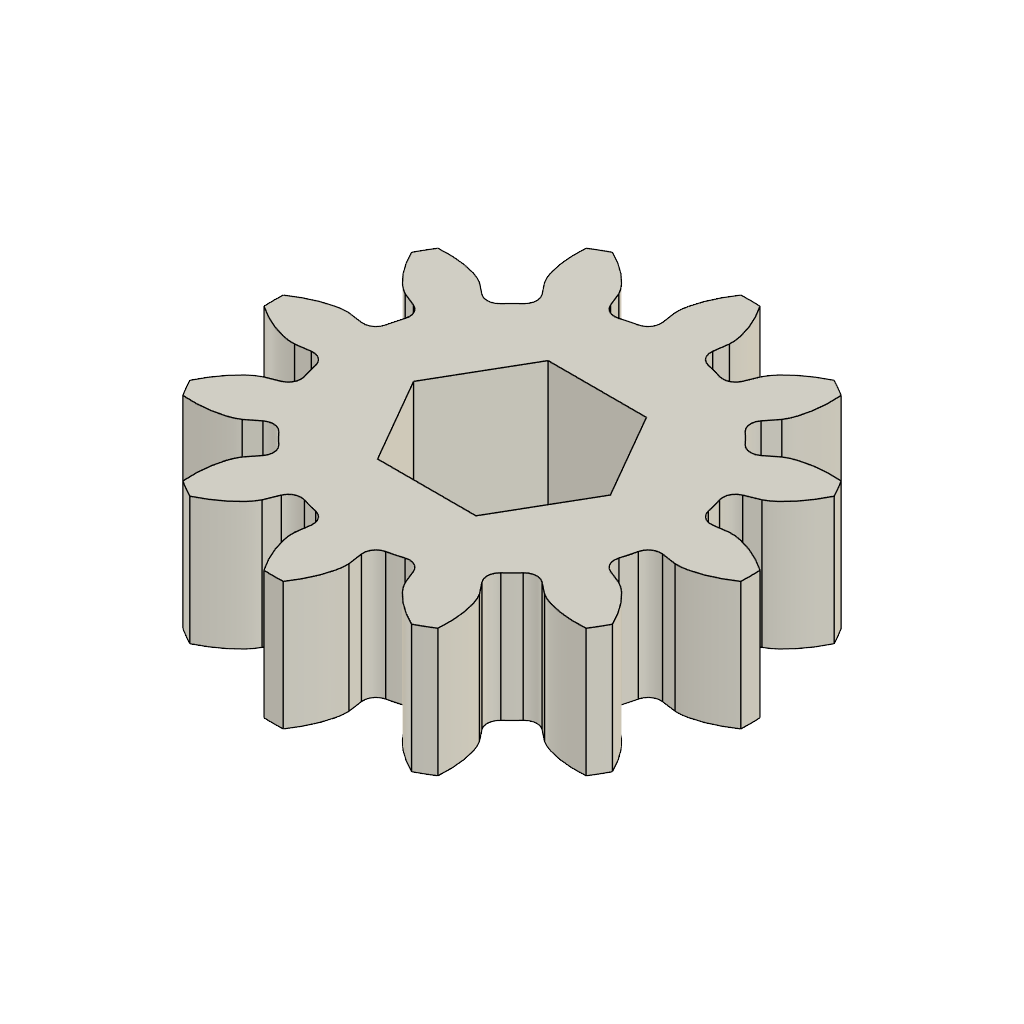
Top_Assembly_103026 (Autodesk Fusion 360 archive; units mm, degrees)
design "1.6M 12T W6 main brush driver"
description: Spur Gear; Module: 1.6; Num Teeth: 12; Pressure Angle: 20.0; Backlash: 0.15 mm
part number: 2026-10-17-22-01-23-754
Autodesk Fusion 360 part; units mm, degrees
note: some values were not read from the file. Set by a fixed rule: which face or edge a step refers to.
sketch "Base Circle" plane through (0, 0, 0) normal (0, 0, 1) x (1, 0, 0)
  circle A0 centre (0, 0) radius 7.7488
  circle A1 centre (0, 0) radius 2 construction
  circle A2 centre (0, 0) radius 4.6188 construction
  line L0 (0, 0) -> (4.6188, 0) construction
  line L1 (4.6188, 0) -> (2.3094, 4)
  line L2 (2.3094, 4) -> (-2.3094, 4)
  line L3 (-2.3094, 4) -> (-4.6188, 0)
  line L4 (0, 0) -> (-4.6188, 0) construction
  line L5 (-2.3094, -4) -> (-4.6188, 0)
  line L6 (2.3094, -4) -> (-2.3094, -4)
  line L7 (4.6188, 0) -> (2.3094, -4)
  circle A3 centre (0, 0) radius 4 construction
  dimension "d4" = 2
  dimension "d5" = 7.7488
  dimension "d9" = 4
  constraint coincident A0.centre A1.centre
  constraint concentric A0 A2
  constraint coincident A2 L0.end
  constraint horizontal L0
  constraint parallel L0 L2
  constraint coincident A2 L3.end
  constraint equal L2 L3
  constraint equal L1 L2
  constraint parallel L0 L4
  constraint coincident L3.end L4.end
  constraint coincident A2 L2.end
  constraint symmetric L0 L1.end L6.start
  constraint symmetric L0 L2.end L5.start
  constraint symmetric L0 L3.end L4.end
  constraint concentric A2 A3
  constraint tangent L1 A3
  measures "d4" radius of A1
  measures "d5" radius of A0
  measures "d9" radius of A3
extrude "Extrude1" add sketch "Base Circle" along normal blind 6
sketch "Gear Tooth" plane through (0, 0, 0) normal (0, 0, 1) x (1, 0, 0)
  spline S0 degree 5 poles (8.9304, -1.2758) (8.9368, -1.2767) (8.9495, -1.2783) (8.9687, -1.2801) (8.9945, -1.2814) (9.0267, -1.2814) (9.0591, -1.2802) (9.0915, -1.2784) (9.124, -1.2761) (9.1565, -1.2736) (9.1891, -1.2708) (9.2216, -1.2676) (9.2542, -1.264) (9.2869, -1.2598) (9.3195, -1.255) (9.3522, -1.2497) (9.3849, -1.2439) (9.4176, -1.2378) (9.4504, -1.2313) (9.4831, -1.2245) (9.5159, -1.2174) (9.5486, -1.21) (9.5813, -1.2022) (9.6141, -1.194) (9.6468, -1.1855) (9.6796, -1.1766) (9.7123, -1.1674) (9.7451, -1.1579) (9.7778, -1.1481) (9.8105, -1.138) (9.8432, -1.1276) (9.8759, -1.1169) (9.9086, -1.1059) (9.9413, -1.0947) (9.9739, -1.0831) (10.0066, -1.0712) (10.0392, -1.0591) (10.0718, -1.0466) (10.1043, -1.0339) (10.1369, -1.021) (10.1694, -1.0077) (10.2019, -0.9942) (10.2344, -0.9804) (10.2668, -0.9664) (10.2993, -0.9521) (10.3316, -0.9375) (10.364, -0.9227) (10.3963, -0.9076) (10.4286, -0.8923) (10.4609, -0.8767) (10.4931, -0.8609) (10.5253, -0.8448) (10.5574, -0.8285) (10.5895, -0.812) (10.6216, -0.7952) (10.6536, -0.7781) (10.6856, -0.7608) (10.7175, -0.7433) (10.7494, -0.7256) (10.7813, -0.7076) (10.8131, -0.6893) (10.8449, -0.6709) (10.8766, -0.6522) (10.9082, -0.6333) (10.9399, -0.6141) (10.9714, -0.5948) (11.0029, -0.5752) (11.0344, -0.5553) (11.0658, -0.5353) (11.0971, -0.515) (11.1284, -0.4945) (11.1534, -0.478) (11.1721, -0.4654) (11.1846, -0.4571) (11.1908, -0.4528) knots 0 0 0 0 0 0 0.01428571 0.02857143 0.04285714 0.05714286 0.07142857 0.08571429 0.1 0.11428571 0.12857143 0.14285714 0.15714286 0.17142857 0.18571429 0.2 0.21428571 0.22857143 0.24285714 0.25714286 0.27142857 0.28571429 0.3 0.31428571 0.32857143 0.34285714 0.35714286 0.37142857 0.38571429 0.4 0.41428571 0.42857143 0.44285714 0.45714286 0.47142857 0.48571429 0.5 0.51428571 0.52857143 0.54285714 0.55714286 0.57142857 0.58571429 0.6 0.61428571 0.62857143 0.64285714 0.65714286 0.67142857 0.68571429 0.7 0.71428571 0.72857143 0.74285714 0.75714286 0.77142857 0.78571429 0.8 0.81428571 0.82857143 0.84285714 0.85714286 0.87142857 0.88571429 0.9 0.91428571 0.92857143 0.94285714 0.95714286 0.97142857 0.98571429 1 1 1 1 1 1
  spline S1 degree 5 poles (8.9304, 1.2758) (8.9368, 1.2767) (8.9495, 1.2783) (8.9687, 1.2801) (8.9945, 1.2814) (9.0267, 1.2814) (9.0591, 1.2802) (9.0915, 1.2784) (9.124, 1.2761) (9.1565, 1.2736) (9.1891, 1.2708) (9.2216, 1.2676) (9.2542, 1.264) (9.2869, 1.2598) (9.3195, 1.255) (9.3522, 1.2497) (9.3849, 1.2439) (9.4176, 1.2378) (9.4504, 1.2313) (9.4831, 1.2245) (9.5159, 1.2174) (9.5486, 1.21) (9.5813, 1.2022) (9.6141, 1.194) (9.6468, 1.1855) (9.6796, 1.1766) (9.7123, 1.1674) (9.7451, 1.1579) (9.7778, 1.1481) (9.8105, 1.138) (9.8432, 1.1276) (9.8759, 1.1169) (9.9086, 1.1059) (9.9413, 1.0947) (9.9739, 1.0831) (10.0066, 1.0712) (10.0392, 1.0591) (10.0718, 1.0466) (10.1043, 1.0339) (10.1369, 1.021) (10.1694, 1.0077) (10.2019, 0.9942) (10.2344, 0.9804) (10.2668, 0.9664) (10.2993, 0.9521) (10.3316, 0.9375) (10.364, 0.9227) (10.3963, 0.9076) (10.4286, 0.8923) (10.4609, 0.8767) (10.4931, 0.8609) (10.5253, 0.8448) (10.5574, 0.8285) (10.5895, 0.812) (10.6216, 0.7952) (10.6536, 0.7781) (10.6856, 0.7608) (10.7175, 0.7433) (10.7494, 0.7256) (10.7813, 0.7076) (10.8131, 0.6893) (10.8449, 0.6709) (10.8766, 0.6522) (10.9082, 0.6333) (10.9399, 0.6141) (10.9714, 0.5948) (11.0029, 0.5752) (11.0344, 0.5553) (11.0658, 0.5353) (11.0971, 0.515) (11.1284, 0.4945) (11.1534, 0.478) (11.1721, 0.4654) (11.1846, 0.4571) (11.1908, 0.4528) knots 0 0 0 0 0 0 0.01428571 0.02857143 0.04285714 0.05714286 0.07142857 0.08571429 0.1 0.11428571 0.12857143 0.14285714 0.15714286 0.17142857 0.18571429 0.2 0.21428571 0.22857143 0.24285714 0.25714286 0.27142857 0.28571429 0.3 0.31428571 0.32857143 0.34285714 0.35714286 0.37142857 0.38571429 0.4 0.41428571 0.42857143 0.44285714 0.45714286 0.47142857 0.48571429 0.5 0.51428571 0.52857143 0.54285714 0.55714286 0.57142857 0.58571429 0.6 0.61428571 0.62857143 0.64285714 0.65714286 0.67142857 0.68571429 0.7 0.71428571 0.72857143 0.74285714 0.75714286 0.77142857 0.78571429 0.8 0.81428571 0.82857143 0.84285714 0.85714286 0.87142857 0.88571429 0.9 0.91428571 0.92857143 0.94285714 0.95714286 0.97142857 0.98571429 1 1 1 1 1 1
  arc A0 (11.1908, -0.4528) -> (11.1908, 0.4528) centre (0, 0) ccw
  line L0 (7.661, -1.0944) -> (8.9304, -1.2758)
  line L1 (7.661, 1.0944) -> (8.9304, 1.2758)
  line L2 (7.661, -1.0944) -> (7.661, 1.0944)
  arc A1 (11.1908, 0.4528) -> (11.1908, -0.4528) centre (0, 0) ccw construction
  point P0 (9.0872, -1.2785)
  point P1 (9.2462, -1.2648)
  point P2 (9.4066, -1.2398)
  point P3 (9.568, -1.2053)
  point P4 (9.7301, -1.1623)
  point P5 (9.8927, -1.1113)
  point P6 (10.0556, -1.0528)
  point P7 (10.2186, -0.9871)
  point P8 (10.3816, -0.9145)
  point P9 (10.5444, -0.8351)
  point P10 (10.7069, -0.7491)
  point P11 (10.8689, -0.6567)
  point P12 (11.0303, -0.5579)
  point P13 (9.0872, 1.2785)
  point P14 (9.2462, 1.2648)
  point P15 (9.4066, 1.2398)
  point P16 (9.568, 1.2053)
  point P17 (9.7301, 1.1623)
  point P18 (9.8927, 1.1113)
  point P19 (10.0556, 1.0528)
  point P20 (10.2186, 0.9871)
  point P21 (10.3816, 0.9145)
  point P22 (10.5444, 0.8351)
  point P23 (10.7069, 0.7491)
  point P24 (10.8689, 0.6567)
  point P25 (11.0303, 0.5579)
  dimension "d3" = 11.2
  constraint coincident S1.end A0.end
  constraint coincident S0.end A0.start
  constraint coincident A0.centre A1.centre
  measures "d3" radius of A1
extrude "Extrude2" add sketch "Gear Tooth" along normal blind 6
fillet "Fillet1" radius 0.6 2 edges at (7.6709, -1.0959, 3) (7.6709, 1.0959, 3)
pattern_circular "C-Pattern1" count 12 over 360 about axis through (0, 0, 1.75) along (0, 0, 1) of "Extrude2", "Fillet1"
sketch "Diametrial Pitch Circle" plane through (0, 0, 0) normal (0, 0, 1) x (1, 0, 0)
  circle A0 centre (0, 0) radius 9.6 construction

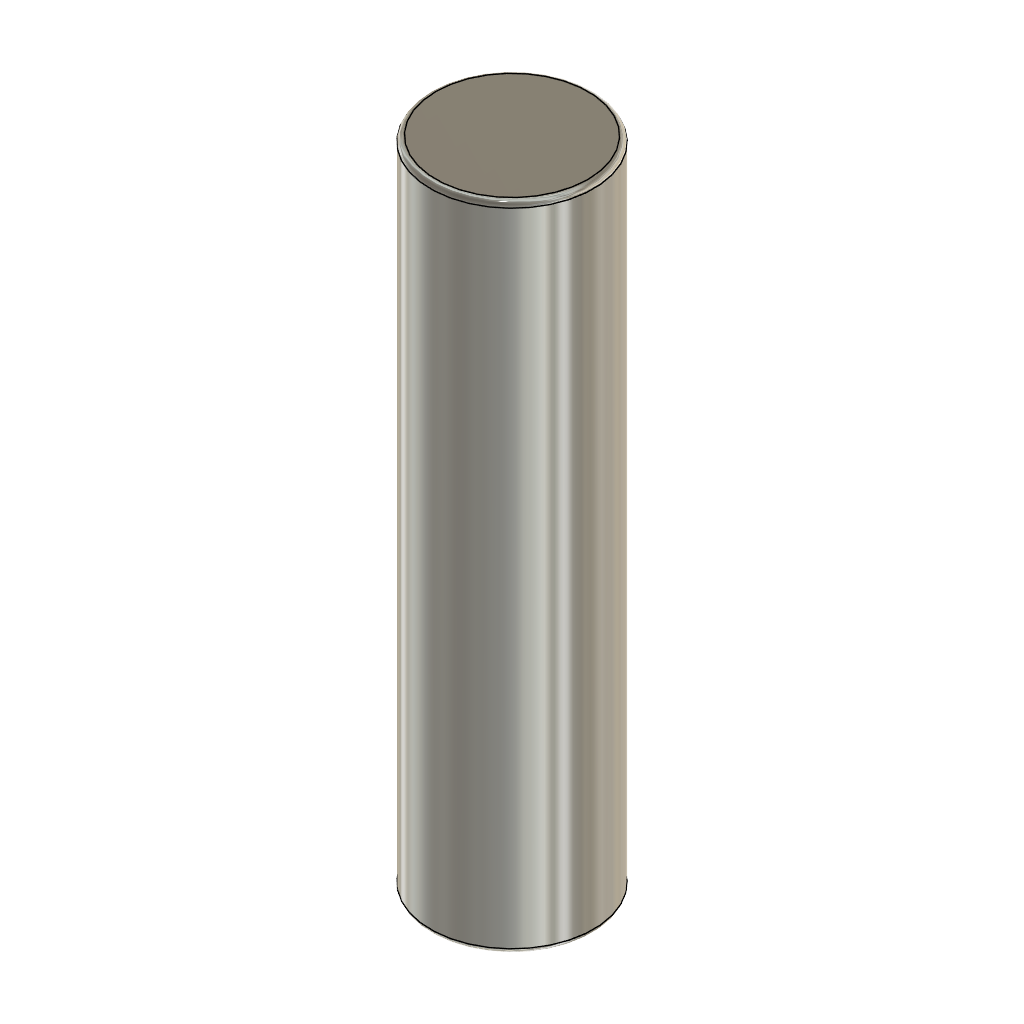
design "Dowel Pin D3 L12"
part number: 2026-10-20-12-42-43-443
Autodesk Fusion 360 part; units mm, degrees
sketch "Sketch1" plane through (0, 0, 0) normal (0, 0, 1) x (1, 0, 0)
  circle A0 centre (0, 0) radius 1.5
  dimension "d2" = 1.5
  constraint coincident A0.centre origin
  measures "d2" radius of A0
extrude "Extrude1" add sketch "Sketch1" along normal blind 12
fillet "Fillet1" radius 0.1 2 edges at (-1.3985, -0.5424, 12) (-1.3985, -0.5424, 0)

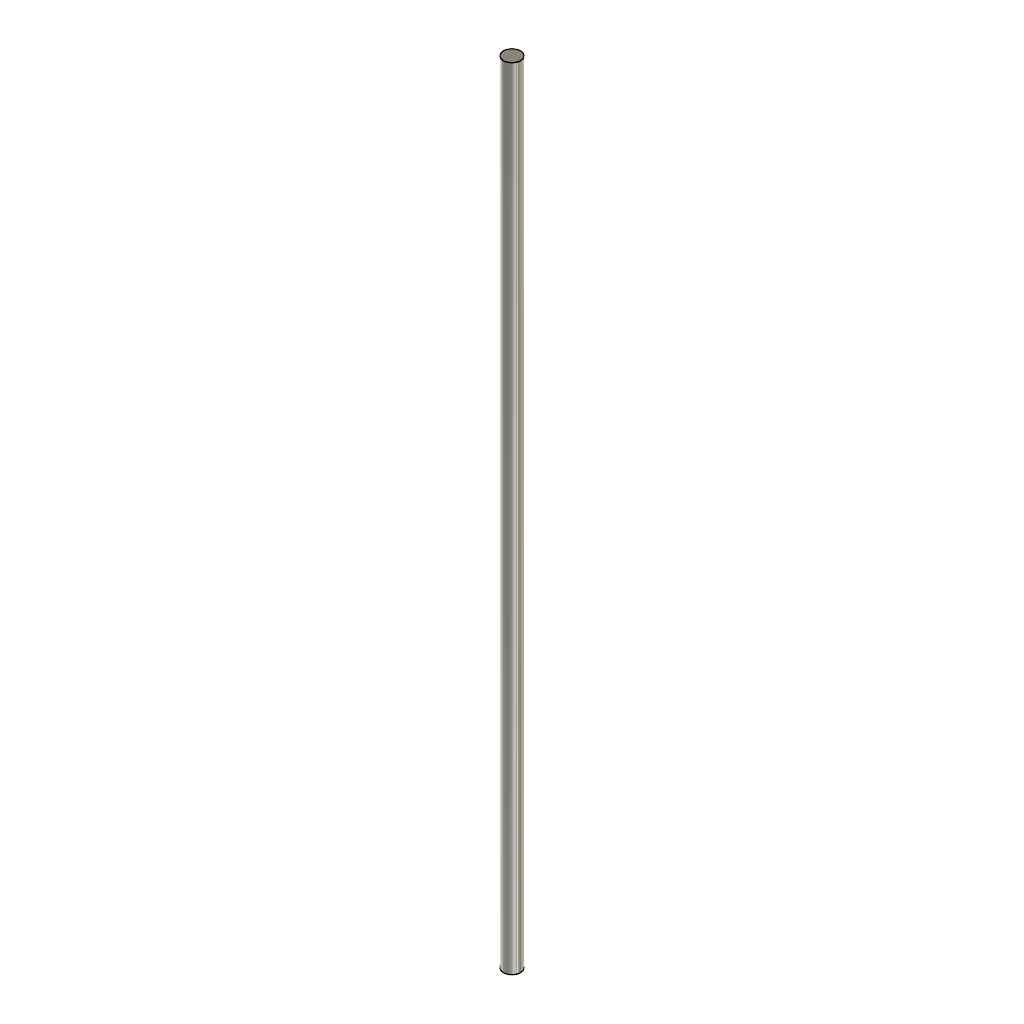
design "Rod"
part number: 2026-10-20-19-00-02-844
Autodesk Fusion 360 part; units mm, degrees
sketch "Sketch1" plane through (0, 0, 0) normal (0, 0, 1) x (1, 0, 0)
  circle A0 centre (0, 0) radius 1.9
  dimension "d1" = 3.8
  constraint coincident A0.centre origin
  measures "d1" diameter of A0
extrude "Extrude1" add sketch "Sketch1" along normal blind 173.85
fillet "Fillet1" radius 0.1 1 edges at (-1.7714, -0.6871, 0)

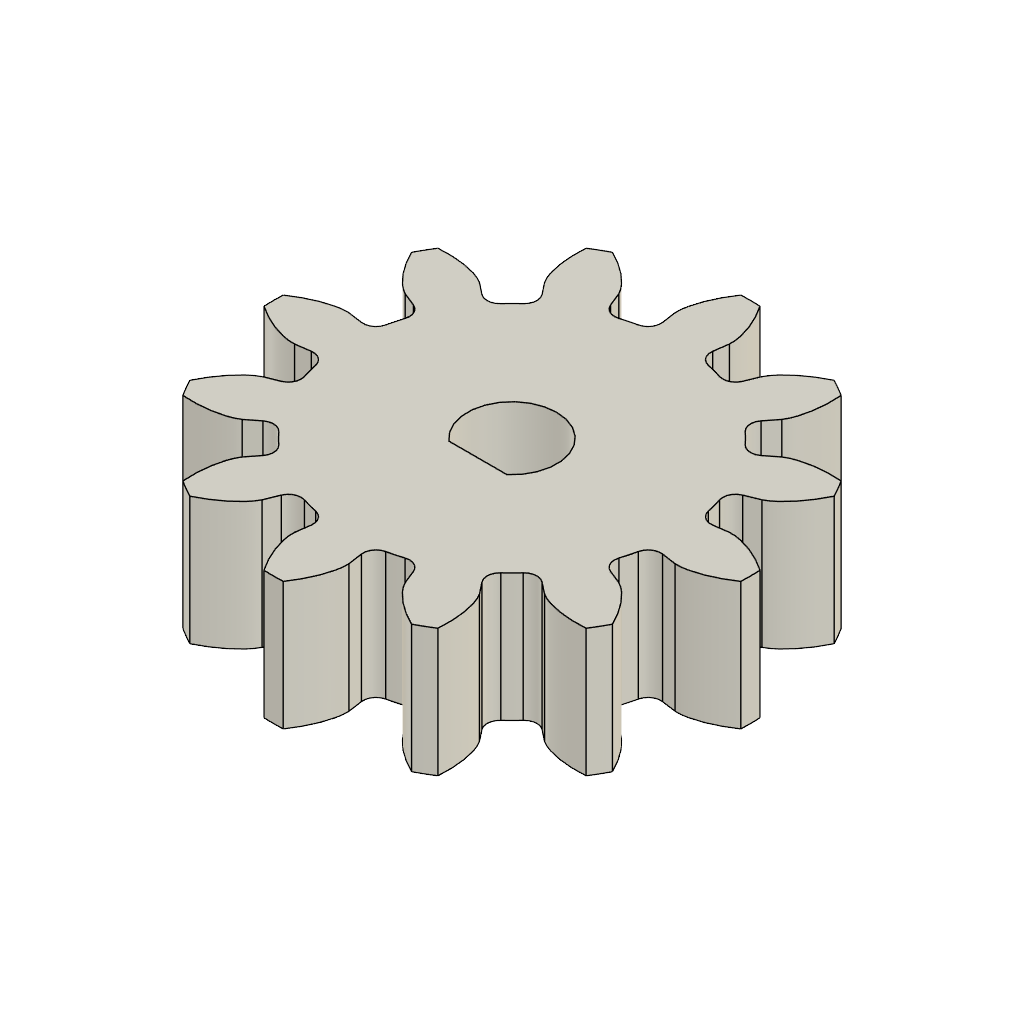
design "1.6M 12T D4"
description: Spur Gear; Module: 1.6; Num Teeth: 12; Pressure Angle: 20.0; Backlash: 0.15 mm
part number: 2026-10-17-22-01-23-754
Autodesk Fusion 360 part; units mm, degrees
sketch "Base Circle" plane through (0, 0, 0) normal (0, 0, 1) x (1, 0, 0)
  circle A0 centre (0, 0) radius 7.7488
  circle A1 centre (0, 0) radius 2 construction
  line L0 (-1.3601, -1.6) -> (1.3601, -1.6)
  line L1 (0, 0) -> (0, -1.6) construction
  arc A2 (1.3601, -1.6) -> (-1.3601, -1.6) centre (0, 0) ccw
  dimension "d1" = 15.4976
  dimension "d2" = 4
  dimension "d4" = 2.1
  dimension "d5" = 1.6
  constraint coincident A0.centre A1.centre
  constraint horizontal L0
  constraint midpoint L0 L1.end
  constraint perpendicular L0 L1
  measures "d1" diameter of A0
  measures "d2" diameter of A1
  measures "d4" radius of A2
  measures "d5" distance of A0.centre L1.end
extrude "Extrude1" add sketch "Base Circle" along normal blind 6
sketch "Gear Tooth" plane through (0, 0, 0) normal (0, 0, 1) x (1, 0, 0)
  spline S0 degree 5 poles (8.9304, -1.2758) (8.9368, -1.2767) (8.9495, -1.2783) (8.9687, -1.2801) (8.9945, -1.2814) (9.0267, -1.2814) (9.0591, -1.2802) (9.0915, -1.2784) (9.124, -1.2761) (9.1565, -1.2736) (9.1891, -1.2708) (9.2216, -1.2676) (9.2542, -1.264) (9.2869, -1.2598) (9.3195, -1.255) (9.3522, -1.2497) (9.3849, -1.2439) (9.4176, -1.2378) (9.4504, -1.2313) (9.4831, -1.2245) (9.5159, -1.2174) (9.5486, -1.21) (9.5813, -1.2022) (9.6141, -1.194) (9.6468, -1.1855) (9.6796, -1.1766) (9.7123, -1.1674) (9.7451, -1.1579) (9.7778, -1.1481) (9.8105, -1.138) (9.8432, -1.1276) (9.8759, -1.1169) (9.9086, -1.1059) (9.9413, -1.0947) (9.9739, -1.0831) (10.0066, -1.0712) (10.0392, -1.0591) (10.0718, -1.0466) (10.1043, -1.0339) (10.1369, -1.021) (10.1694, -1.0077) (10.2019, -0.9942) (10.2344, -0.9804) (10.2668, -0.9664) (10.2993, -0.9521) (10.3316, -0.9375) (10.364, -0.9227) (10.3963, -0.9076) (10.4286, -0.8923) (10.4609, -0.8767) (10.4931, -0.8609) (10.5253, -0.8448) (10.5574, -0.8285) (10.5895, -0.812) (10.6216, -0.7952) (10.6536, -0.7781) (10.6856, -0.7608) (10.7175, -0.7433) (10.7494, -0.7256) (10.7813, -0.7076) (10.8131, -0.6893) (10.8449, -0.6709) (10.8766, -0.6522) (10.9082, -0.6333) (10.9399, -0.6141) (10.9714, -0.5948) (11.0029, -0.5752) (11.0344, -0.5553) (11.0658, -0.5353) (11.0971, -0.515) (11.1284, -0.4945) (11.1534, -0.478) (11.1721, -0.4654) (11.1846, -0.4571) (11.1908, -0.4528) knots 0 0 0 0 0 0 0.01428571 0.02857143 0.04285714 0.05714286 0.07142857 0.08571429 0.1 0.11428571 0.12857143 0.14285714 0.15714286 0.17142857 0.18571429 0.2 0.21428571 0.22857143 0.24285714 0.25714286 0.27142857 0.28571429 0.3 0.31428571 0.32857143 0.34285714 0.35714286 0.37142857 0.38571429 0.4 0.41428571 0.42857143 0.44285714 0.45714286 0.47142857 0.48571429 0.5 0.51428571 0.52857143 0.54285714 0.55714286 0.57142857 0.58571429 0.6 0.61428571 0.62857143 0.64285714 0.65714286 0.67142857 0.68571429 0.7 0.71428571 0.72857143 0.74285714 0.75714286 0.77142857 0.78571429 0.8 0.81428571 0.82857143 0.84285714 0.85714286 0.87142857 0.88571429 0.9 0.91428571 0.92857143 0.94285714 0.95714286 0.97142857 0.98571429 1 1 1 1 1 1
  spline S1 degree 5 poles (8.9304, 1.2758) (8.9368, 1.2767) (8.9495, 1.2783) (8.9687, 1.2801) (8.9945, 1.2814) (9.0267, 1.2814) (9.0591, 1.2802) (9.0915, 1.2784) (9.124, 1.2761) (9.1565, 1.2736) (9.1891, 1.2708) (9.2216, 1.2676) (9.2542, 1.264) (9.2869, 1.2598) (9.3195, 1.255) (9.3522, 1.2497) (9.3849, 1.2439) (9.4176, 1.2378) (9.4504, 1.2313) (9.4831, 1.2245) (9.5159, 1.2174) (9.5486, 1.21) (9.5813, 1.2022) (9.6141, 1.194) (9.6468, 1.1855) (9.6796, 1.1766) (9.7123, 1.1674) (9.7451, 1.1579) (9.7778, 1.1481) (9.8105, 1.138) (9.8432, 1.1276) (9.8759, 1.1169) (9.9086, 1.1059) (9.9413, 1.0947) (9.9739, 1.0831) (10.0066, 1.0712) (10.0392, 1.0591) (10.0718, 1.0466) (10.1043, 1.0339) (10.1369, 1.021) (10.1694, 1.0077) (10.2019, 0.9942) (10.2344, 0.9804) (10.2668, 0.9664) (10.2993, 0.9521) (10.3316, 0.9375) (10.364, 0.9227) (10.3963, 0.9076) (10.4286, 0.8923) (10.4609, 0.8767) (10.4931, 0.8609) (10.5253, 0.8448) (10.5574, 0.8285) (10.5895, 0.812) (10.6216, 0.7952) (10.6536, 0.7781) (10.6856, 0.7608) (10.7175, 0.7433) (10.7494, 0.7256) (10.7813, 0.7076) (10.8131, 0.6893) (10.8449, 0.6709) (10.8766, 0.6522) (10.9082, 0.6333) (10.9399, 0.6141) (10.9714, 0.5948) (11.0029, 0.5752) (11.0344, 0.5553) (11.0658, 0.5353) (11.0971, 0.515) (11.1284, 0.4945) (11.1534, 0.478) (11.1721, 0.4654) (11.1846, 0.4571) (11.1908, 0.4528) knots 0 0 0 0 0 0 0.01428571 0.02857143 0.04285714 0.05714286 0.07142857 0.08571429 0.1 0.11428571 0.12857143 0.14285714 0.15714286 0.17142857 0.18571429 0.2 0.21428571 0.22857143 0.24285714 0.25714286 0.27142857 0.28571429 0.3 0.31428571 0.32857143 0.34285714 0.35714286 0.37142857 0.38571429 0.4 0.41428571 0.42857143 0.44285714 0.45714286 0.47142857 0.48571429 0.5 0.51428571 0.52857143 0.54285714 0.55714286 0.57142857 0.58571429 0.6 0.61428571 0.62857143 0.64285714 0.65714286 0.67142857 0.68571429 0.7 0.71428571 0.72857143 0.74285714 0.75714286 0.77142857 0.78571429 0.8 0.81428571 0.82857143 0.84285714 0.85714286 0.87142857 0.88571429 0.9 0.91428571 0.92857143 0.94285714 0.95714286 0.97142857 0.98571429 1 1 1 1 1 1
  arc A0 (11.1908, -0.4528) -> (11.1908, 0.4528) centre (0, 0) ccw
  line L0 (7.661, -1.0944) -> (8.9304, -1.2758)
  line L1 (7.661, 1.0944) -> (8.9304, 1.2758)
  line L2 (7.661, -1.0944) -> (7.661, 1.0944)
  arc A1 (11.1908, 0.4528) -> (11.1908, -0.4528) centre (0, 0) ccw construction
  point P0 (9.0872, -1.2785)
  point P1 (9.2462, -1.2648)
  point P2 (9.4066, -1.2398)
  point P3 (9.568, -1.2053)
  point P4 (9.7301, -1.1623)
  point P5 (9.8927, -1.1113)
  point P6 (10.0556, -1.0528)
  point P7 (10.2186, -0.9871)
  point P8 (10.3816, -0.9145)
  point P9 (10.5444, -0.8351)
  point P10 (10.7069, -0.7491)
  point P11 (10.8689, -0.6567)
  point P12 (11.0303, -0.5579)
  point P13 (9.0872, 1.2785)
  point P14 (9.2462, 1.2648)
  point P15 (9.4066, 1.2398)
  point P16 (9.568, 1.2053)
  point P17 (9.7301, 1.1623)
  point P18 (9.8927, 1.1113)
  point P19 (10.0556, 1.0528)
  point P20 (10.2186, 0.9871)
  point P21 (10.3816, 0.9145)
  point P22 (10.5444, 0.8351)
  point P23 (10.7069, 0.7491)
  point P24 (10.8689, 0.6567)
  point P25 (11.0303, 0.5579)
  dimension "d3" = 11.2
  constraint coincident S1.end A0.end
  constraint coincident S0.end A0.start
  constraint coincident A0.centre A1.centre
  measures "d3" radius of A1
extrude "Extrude2" add sketch "Gear Tooth" along normal blind 6
fillet "Fillet1" radius 0.6 2 edges at (7.6709, -1.0959, 3) (7.6709, 1.0959, 3)
pattern_circular "C-Pattern1" count 12 over 360 about axis through (0, 0, 1.75) along (0, 0, 1) of "Extrude2", "Fillet1"
sketch "Diametrial Pitch Circle" plane through (0, 0, 0) normal (0, 0, 1) x (1, 0, 0)
  circle A0 centre (0, 0) radius 9.6 construction

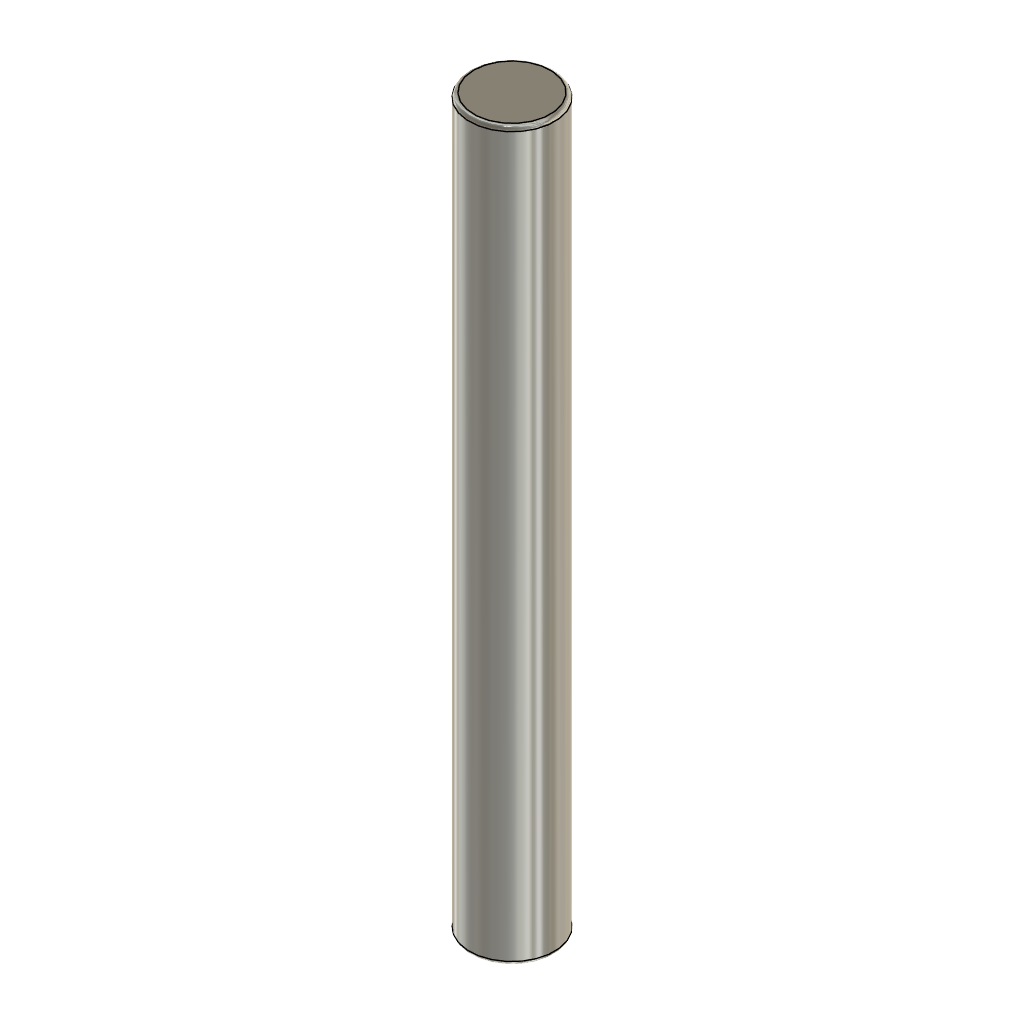
design "Pin 4 x 34.2"
part number: 2026-10-28-22-08-27-820
Autodesk Fusion 360 part; units mm, degrees
sketch "Sketch1" plane through (0, 0, 0) normal (0, 0, 1) x (1, 0, 0)
  circle A0 centre (0, 0) radius 2
  dimension "d1" = 4
  constraint coincident A0.centre origin
  measures "d1" diameter of A0
extrude "Extrude1" add sketch "Sketch1" along normal blind 34.2
fillet "Fillet1" radius 0.2 2 edges at (-1.8647, -0.7232, 34.2) (-1.8647, -0.7232, 0)

design "Brush Rod Tip"
part number: 2026-10-14-02-04-19-763
Autodesk Fusion 360 part; units mm, degrees
sketch "Dimensions" plane through (0, 0, 0) normal (0, 0, 1) x (1, 0, 0)
  circle A0 centre (0, 0) radius 1
  circle A1 centre (0, 0) radius 1.3
  circle A2 centre (0, 0) radius 1.9
  circle A3 centre (0, 0) radius 2.5
  dimension "d2" = 1
  dimension "d4" = 1.3
  dimension "d6" = 1.9
  dimension "d8" = 2.5
  constraint coincident A0.centre A1.centre
  constraint concentric A1 A3
  measures "d2" radius of A0
  measures "d4" radius of A1
  measures "d6" radius of A2
  measures "d8" radius of A3
extrude "Extrude1" add sketch "Dimensions" against normal blind 3 contours A3
extrude "Extrude2" add sketch "Dimensions" along normal blind 6.8 contours A0 | A1 | A2 | A3
extrude "Extrude3" add sketch "Dimensions" along normal blind 1.4 from surface at 6.8 contours A0
extrude "Extrude4" add sketch "Dimensions" along normal blind 2 from surface at 8.2 contours A0 | A1
chamfer "Chamfer1" distance 0.4 angle 45 1 edges at (-0.9323, 0.3616, 6.8) tangent chain off
chamfer "Chamfer1" distance 0.3 angle 45 1 edges at (-0.9323, -0.3616, 8.2) tangent chain off
chamfer "Chamfer1" distance 1 angle 45 1 edges at (-1.212, -0.4701, 10.2) tangent chain off
equation "d11 = 2.3 mm + 4.5 mm"

design "1.6M 12T A3.2 W6"
description: Spur Gear; Module: 1.6; Num Teeth: 12; Pressure Angle: 20.0; Backlash: 0.15 mm
part number: 2026-10-17-22-01-23-754
Autodesk Fusion 360 part; units mm, degrees
sketch "Base Circle" plane through (0, 0, 0) normal (0, 0, 1) x (1, 0, 0)
  circle A0 centre (0, 0) radius 7.7488
  circle A1 centre (0, 0) radius 1.6
  dimension "d1" = 15.4976
  dimension "d2" = 3.2
  constraint coincident A0.centre A1.centre
  measures "d1" diameter of A0
  measures "d2" diameter of A1
extrude "Extrude1" add sketch "Base Circle" along normal blind 6
sketch "Gear Tooth" plane through (0, 0, 0) normal (0, 0, 1) x (1, 0, 0)
  spline S0 degree 5 poles (8.9304, -1.2758) (8.9368, -1.2767) (8.9495, -1.2783) (8.9687, -1.2801) (8.9945, -1.2814) (9.0267, -1.2814) (9.0591, -1.2802) (9.0915, -1.2784) (9.124, -1.2761) (9.1565, -1.2736) (9.1891, -1.2708) (9.2216, -1.2676) (9.2542, -1.264) (9.2869, -1.2598) (9.3195, -1.255) (9.3522, -1.2497) (9.3849, -1.2439) (9.4176, -1.2378) (9.4504, -1.2313) (9.4831, -1.2245) (9.5159, -1.2174) (9.5486, -1.21) (9.5813, -1.2022) (9.6141, -1.194) (9.6468, -1.1855) (9.6796, -1.1766) (9.7123, -1.1674) (9.7451, -1.1579) (9.7778, -1.1481) (9.8105, -1.138) (9.8432, -1.1276) (9.8759, -1.1169) (9.9086, -1.1059) (9.9413, -1.0947) (9.9739, -1.0831) (10.0066, -1.0712) (10.0392, -1.0591) (10.0718, -1.0466) (10.1043, -1.0339) (10.1369, -1.021) (10.1694, -1.0077) (10.2019, -0.9942) (10.2344, -0.9804) (10.2668, -0.9664) (10.2993, -0.9521) (10.3316, -0.9375) (10.364, -0.9227) (10.3963, -0.9076) (10.4286, -0.8923) (10.4609, -0.8767) (10.4931, -0.8609) (10.5253, -0.8448) (10.5574, -0.8285) (10.5895, -0.812) (10.6216, -0.7952) (10.6536, -0.7781) (10.6856, -0.7608) (10.7175, -0.7433) (10.7494, -0.7256) (10.7813, -0.7076) (10.8131, -0.6893) (10.8449, -0.6709) (10.8766, -0.6522) (10.9082, -0.6333) (10.9399, -0.6141) (10.9714, -0.5948) (11.0029, -0.5752) (11.0344, -0.5553) (11.0658, -0.5353) (11.0971, -0.515) (11.1284, -0.4945) (11.1534, -0.478) (11.1721, -0.4654) (11.1846, -0.4571) (11.1908, -0.4528) knots 0 0 0 0 0 0 0.01428571 0.02857143 0.04285714 0.05714286 0.07142857 0.08571429 0.1 0.11428571 0.12857143 0.14285714 0.15714286 0.17142857 0.18571429 0.2 0.21428571 0.22857143 0.24285714 0.25714286 0.27142857 0.28571429 0.3 0.31428571 0.32857143 0.34285714 0.35714286 0.37142857 0.38571429 0.4 0.41428571 0.42857143 0.44285714 0.45714286 0.47142857 0.48571429 0.5 0.51428571 0.52857143 0.54285714 0.55714286 0.57142857 0.58571429 0.6 0.61428571 0.62857143 0.64285714 0.65714286 0.67142857 0.68571429 0.7 0.71428571 0.72857143 0.74285714 0.75714286 0.77142857 0.78571429 0.8 0.81428571 0.82857143 0.84285714 0.85714286 0.87142857 0.88571429 0.9 0.91428571 0.92857143 0.94285714 0.95714286 0.97142857 0.98571429 1 1 1 1 1 1
  spline S1 degree 5 poles (8.9304, 1.2758) (8.9368, 1.2767) (8.9495, 1.2783) (8.9687, 1.2801) (8.9945, 1.2814) (9.0267, 1.2814) (9.0591, 1.2802) (9.0915, 1.2784) (9.124, 1.2761) (9.1565, 1.2736) (9.1891, 1.2708) (9.2216, 1.2676) (9.2542, 1.264) (9.2869, 1.2598) (9.3195, 1.255) (9.3522, 1.2497) (9.3849, 1.2439) (9.4176, 1.2378) (9.4504, 1.2313) (9.4831, 1.2245) (9.5159, 1.2174) (9.5486, 1.21) (9.5813, 1.2022) (9.6141, 1.194) (9.6468, 1.1855) (9.6796, 1.1766) (9.7123, 1.1674) (9.7451, 1.1579) (9.7778, 1.1481) (9.8105, 1.138) (9.8432, 1.1276) (9.8759, 1.1169) (9.9086, 1.1059) (9.9413, 1.0947) (9.9739, 1.0831) (10.0066, 1.0712) (10.0392, 1.0591) (10.0718, 1.0466) (10.1043, 1.0339) (10.1369, 1.021) (10.1694, 1.0077) (10.2019, 0.9942) (10.2344, 0.9804) (10.2668, 0.9664) (10.2993, 0.9521) (10.3316, 0.9375) (10.364, 0.9227) (10.3963, 0.9076) (10.4286, 0.8923) (10.4609, 0.8767) (10.4931, 0.8609) (10.5253, 0.8448) (10.5574, 0.8285) (10.5895, 0.812) (10.6216, 0.7952) (10.6536, 0.7781) (10.6856, 0.7608) (10.7175, 0.7433) (10.7494, 0.7256) (10.7813, 0.7076) (10.8131, 0.6893) (10.8449, 0.6709) (10.8766, 0.6522) (10.9082, 0.6333) (10.9399, 0.6141) (10.9714, 0.5948) (11.0029, 0.5752) (11.0344, 0.5553) (11.0658, 0.5353) (11.0971, 0.515) (11.1284, 0.4945) (11.1534, 0.478) (11.1721, 0.4654) (11.1846, 0.4571) (11.1908, 0.4528) knots 0 0 0 0 0 0 0.01428571 0.02857143 0.04285714 0.05714286 0.07142857 0.08571429 0.1 0.11428571 0.12857143 0.14285714 0.15714286 0.17142857 0.18571429 0.2 0.21428571 0.22857143 0.24285714 0.25714286 0.27142857 0.28571429 0.3 0.31428571 0.32857143 0.34285714 0.35714286 0.37142857 0.38571429 0.4 0.41428571 0.42857143 0.44285714 0.45714286 0.47142857 0.48571429 0.5 0.51428571 0.52857143 0.54285714 0.55714286 0.57142857 0.58571429 0.6 0.61428571 0.62857143 0.64285714 0.65714286 0.67142857 0.68571429 0.7 0.71428571 0.72857143 0.74285714 0.75714286 0.77142857 0.78571429 0.8 0.81428571 0.82857143 0.84285714 0.85714286 0.87142857 0.88571429 0.9 0.91428571 0.92857143 0.94285714 0.95714286 0.97142857 0.98571429 1 1 1 1 1 1
  arc A0 (11.1908, -0.4528) -> (11.1908, 0.4528) centre (0, 0) ccw
  line L0 (7.661, -1.0944) -> (8.9304, -1.2758)
  line L1 (7.661, 1.0944) -> (8.9304, 1.2758)
  line L2 (7.661, -1.0944) -> (7.661, 1.0944)
  arc A1 (11.1908, 0.4528) -> (11.1908, -0.4528) centre (0, 0) ccw construction
  point P0 (9.0872, -1.2785)
  point P1 (9.2462, -1.2648)
  point P2 (9.4066, -1.2398)
  point P3 (9.568, -1.2053)
  point P4 (9.7301, -1.1623)
  point P5 (9.8927, -1.1113)
  point P6 (10.0556, -1.0528)
  point P7 (10.2186, -0.9871)
  point P8 (10.3816, -0.9145)
  point P9 (10.5444, -0.8351)
  point P10 (10.7069, -0.7491)
  point P11 (10.8689, -0.6567)
  point P12 (11.0303, -0.5579)
  point P13 (9.0872, 1.2785)
  point P14 (9.2462, 1.2648)
  point P15 (9.4066, 1.2398)
  point P16 (9.568, 1.2053)
  point P17 (9.7301, 1.1623)
  point P18 (9.8927, 1.1113)
  point P19 (10.0556, 1.0528)
  point P20 (10.2186, 0.9871)
  point P21 (10.3816, 0.9145)
  point P22 (10.5444, 0.8351)
  point P23 (10.7069, 0.7491)
  point P24 (10.8689, 0.6567)
  point P25 (11.0303, 0.5579)
  dimension "d3" = 11.2
  constraint coincident S1.end A0.end
  constraint coincident S0.end A0.start
  constraint coincident A0.centre A1.centre
  measures "d3" radius of A1
extrude "Extrude2" add sketch "Gear Tooth" along normal blind 6
fillet "Fillet1" radius 0.6 2 edges at (7.6709, -1.0959, 3) (7.6709, 1.0959, 3)
pattern_circular "C-Pattern1" count 12 over 360 about axis through (0, 0, 0) along (0, 0, 1) of "Extrude2", "Fillet1"
sketch "Diametrial Pitch Circle" plane through (0, 0, 0) normal (0, 0, 1) x (1, 0, 0)
  circle A0 centre (0, 0) radius 9.6 construction

design "JGA25-310"
part number: 2026-10-20-21-35-46-817
Autodesk Fusion 360 part; units mm, degrees
sketch "Sketch1" plane through (0, 0, 0) normal (0, 1, 0) x (1, 0, 0)
  circle A0 centre (0, 0) radius 12.5
  line L0 (0, 0) -> (0, 12.5) construction
  point P0 (0, 12.5)
  dimension "d1" = 25
  constraint coincident A0.centre L0.start
  constraint coincident A0 P0
  constraint vertical L0
  constraint coincident P0 L0.end
  measures "d1" diameter of A0
extrude "Extrude1" add sketch "Sketch1" along normal blind 4.4 makes body 1
extrude "Extrude4" add 1 faces at (-3.3879, 4.4, 0.621) along direction (0, 1, 0) blind 12.4 separate body on bodies 1 makes body 2
extrude "Extrude5" add 1 faces at (-3.3879, 16.8, 0.621) along direction (0, 1, 0) blind 4.2 separate body on bodies 2 makes body 3
sketch "Sketch2" plane through (0, 21, 0) normal (0, 1, 0) x (-1, 0, 0)
  circle A0 centre (0, 0) radius 12.5
  circle A1 centre (0, 0) radius 12.2
  circle A2 centre (0, 0) radius 12.5
  dimension "d6" = 24.4
  constraint coincident A0.centre A1.centre
  measures "d6" diameter of A1
extrude "Extrude3" add sketch "Sketch2" along normal blind 18.4 separate body contours A1 makes body 4
fillet "Fillet1" radius 0.5 1 edges at (11.3744, 21, -4.4117) on bodies 4
sketch "Sketch3" plane through (0, 0, 0) normal (0, -1, 0) x (1, 0, 0)
  circle A0 centre (0, 0) radius 12.5
  circle A1 centre (0, 0) radius 3.5
  circle A2 centre (0, 0) radius 2
  dimension "d15" = 7
  dimension "d18" = 4
  constraint coincident A0.centre A1.centre
  constraint concentric A1 A2
  measures "d15" diameter of A1
  measures "d18" diameter of A2
extrude "Extrude6" add sketch "Sketch3" along normal blind 2.5 separate body contours A1 makes body 5
extrude "Extrude7" add sketch "Sketch3" along normal blind 11.5 separate body contours A2 makes body 6
sketch "Shaft Tip" plane through (0, -11.5, 0) normal (0, -1, 0) x (1, 0, 0)
  circle A0 centre (0, 0) radius 2
  circle A1 centre (0, 0) radius 2
  line L0 (-1.3229, 1.5) -> (1.3229, 1.5)
  dimension "d22" = 1.5
  constraint horizontal L0
  constraint coincident A1 L0.end
  constraint coincident A1 L0.start
  measures "d22" distance of L0 A0.centre
extrude "Extrude8" cut sketch "Shaft Tip" against normal blind 8 contours A0 A1 L0 picked at (-0.3643, 1.5583) bodies 1 6
sketch "Sketch5" plane through (0, 39.4, 0) normal (0, 1, 0) x (-1, 0, 0)
  circle A0 centre (0, 0) radius 12.2
  line L0 (-1.5, 9.7) -> (1.5, 9.7)
  line L1 (1.5, 9.7) -> (1.5, 9.2)
  line L2 (1.5, 9.2) -> (-1.5, 9.2)
  line L3 (-1.5, 9.2) -> (-1.5, 9.7)
  line L4 (0, 9.2) -> (0, 0)
  line L5 (0, 9.7) -> (0, 12.2) construction
  dimension "d25" = 3
  dimension "d26" = 0.5
  dimension "d27" = 3
  constraint horizontal L0
  constraint vertical L1
  constraint horizontal L2
  constraint vertical L3
  constraint midpoint L2 L4.start
  constraint coincident A0.centre L4.end
  constraint vertical L4
  constraint midpoint L0 L5.start
  constraint coincident A0 L5.end
  constraint perpendicular L0 L5
  measures "d25" distance of L0.start L0.end
  measures "d26" distance of L0.end L1.end
  measures "d27" distance of L4.start L5.end
extrude "Extrude9" add sketch "Sketch5" along normal blind 4 separate body contours L0 L1 L2 L3 makes body 7
fillet "Fillet3" radius 1 2 edges at (-1.5, 43.4, 9.45) (1.5, 43.4, 9.45) on bodies 7
sketch "Sketch6" plane through (0, 0, 0) normal (0, -1, 0) x (1, 0, 0)
  circle A0 centre (0, 0) radius 12.5
  line L0 (0, 0) -> (8.5, 0) construction
  line L1 (0, 0) -> (-8.5, 0) construction
  circle A1 centre (8.5, 0) radius 1.5
  circle A2 centre (-8.5, 0) radius 1.5
  dimension "d30" = 3
  dimension "d31" = 17
  constraint coincident A0.centre L0.start
  constraint horizontal L0
  constraint parallel L0 L1
  constraint equal L0 L1
  constraint coincident L0.end A1.centre
  constraint coincident L1.end A2.centre
  constraint equal A1 A2
  measures "d30" diameter of A1
  measures "d31" distance of L0.end L1.end
extrude "Extrude10" cut sketch "Sketch6" against normal through all contours A1 | A2 bodies 1 6
sketch "Sketch7" plane through (0, 39.4, 0) normal (0, 1, 0) x (-1, 0, 0)
  circle A0 centre (0, 0) radius 12.2
  circle A1 centre (0, 0) radius 3.05
  dimension "d34" = 6.1
  constraint coincident A0.centre A1.centre
  measures "d34" diameter of A1
extrude "Extrude11" add sketch "Sketch7" along normal blind 1.3 contours A1 bodies 4
ref_plane "WorkPlane2" through (0, 31.2239, 12.2) normal (0, 0, 1) x (-1, 0, 0)
fillet "Fillet2" radius 0.1 1 edges at (0, -11.5, -2) on bodies 6
mirror "Mirror1" about plane through (0, 0, 0) normal (0, 0, 1) of "Extrude9", "Fillet3" makes body 8
copy_body "Body->Comp1" bodies 6 removing the originals makes body 9 in component "Shaft"
component "Shaft" placed x (1, 0, 0) y (0, 1, 0) z (0, 0, 1) at (0, 0, 0)
equation "d11 = 21 mm - 4.4 mm - 4.2 mm"

design "Smartphone"
Autodesk Fusion 360 part; units mm, degrees
sketch "Body" plane through (0, 0, 0) normal (0, 0, 1) x (1, 0, 0)
  line L0 (-83.45, 39.05) -> (83.45, 39.05)
  line L1 (83.45, 39.05) -> (83.45, -39.05)
  line L2 (83.45, -39.05) -> (-83.45, -39.05)
  line L3 (-83.45, -39.05) -> (-83.45, 39.05)
  line L4 (0, 39.05) -> (0, 0) construction
  line L5 (-83.45, 0) -> (0, 0)
  dimension "d7" = 78.1
  dimension "d11" = 166.9
  constraint horizontal L0
  constraint vertical L1
  constraint horizontal L2
  constraint vertical L3
  constraint midpoint L0 L4.start
  constraint coincident L4.end L5.end
  constraint midpoint L3 L5.start
  constraint horizontal L5
  constraint vertical L4
  measures "d7" distance of L0.end L1.end
  measures "d11" distance of L0.start L0.end
extrude "Extrude1" add sketch "Body" along normal blind 9
sketch "Back Joints" plane through (0, 0, 0) normal (0, 0, -1) x (1, 0, 0)
  line L0 (83.45, 39.05) -> (-83.45, 39.05)
  line L1 (-83.45, 39.05) -> (-83.45, -39.05)
  line L2 (-83.45, -39.05) -> (83.45, -39.05)
  line L3 (83.45, -39.05) -> (83.45, 39.05)
  line L4 (83.45, 39.05) -> (-83.45, 39.05)
  line L5 (-83.45, -39.05) -> (83.45, -39.05)
  line L6 (0, 39.05) -> (0, -39.05) construction
  point P0 (0, -39.05)
  point P1 (0, 39.05)
  constraint midpoint L4 P1
  constraint midpoint L5 P0
  constraint coincident P0 L6.end
  constraint coincident P1 L6.start
fillet "Fillet1" radius 2 7 faces at (27.8167, 0, 9) (27.8167, 0, 0) (27.8167, -39.05, 3) (83.45, 13.0167, 6) (-27.8167, 39.05, 3) (-83.45, -26.0333, 6) (-83.45, 13.0167, 6)
sketch "Face Joints" plane through (0, 0, 9) normal (0, 0, 1) x (-1, 0, 0)
  line L0 (-81.45, 37.05) -> (-81.45, -37.05)
  line L1 (-81.45, -37.05) -> (81.45, -37.05)
  line L2 (81.45, -37.05) -> (81.45, 37.05)
  line L3 (81.45, 37.05) -> (-81.45, 37.05)
  point P0 (0, -39.05)
  point P1 (0, 39.05)
equation "maxPhoneHeight = 166.9 mm"
equation "minPhoneHeight = 131.5 mm"
equation "maxPhoneWidth = 78.1 mm"
equation "minPhoneWidth = 64.2 mm"
equation "maxPhoneDepth = 9 mm"
equation "minPhoneDepth = 7.3 mm"
equation "d7 = phoneWidth"
equation "phoneWidth = maxPhoneWidth"
equation "phoneHeight = maxPhoneHeight"
equation "phoneDepth = maxPhoneDepth"
equation "d11 = phoneHeight"
equation "d12 = phoneDepth"
equation "maxCaseThickness = 5 mm"
